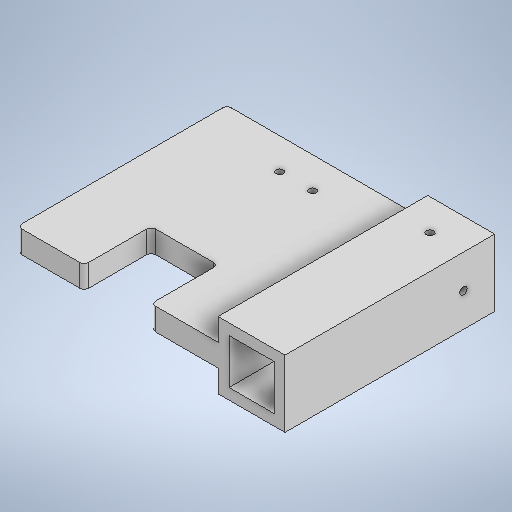
# Autodesk Inventor part: Sujetador_Camara
Saved by Autodesk Inventor 2025.3 (Build 293356030, 356C)
## iProperties
Created: 2026-03-05
Part Number: Sujetador_Camara
Material: Generic
Document SubType Name: Modeling
Designer: pablo
Density: 1 g/cm^3
Appearance: Default
Author: pablo
Autodesk Inventor part; units mm, degrees
ref_plane "YZ Plane" through (0, 0, 0) normal (1, 0, 0) x (0, 1, 0)
ref_plane "XZ Plane" through (0, 0, 0) normal (0, 1, 0) x (-1, 0, 0)
ref_plane "XY Plane" through (0, 0, 0) normal (0, 0, 1) x (1, 0, 0)
sketch "Sketch1" plane through (0, 0, 0) normal (0, 0, 1) x (1, 0, 0)
  line L0 (0, 0) -> (20.2, 0)
  line L1 (20.2, 0) -> (20.2, 20.2)
  line L2 (20.2, 20.2) -> (0, 20.2)
  line L3 (0, 20.2) -> (0, 0)
  line L4 (-4.9, -4.9) -> (25.1, -4.9)
  line L5 (25.1, -4.9) -> (25.1, 25.1)
  line L6 (25.1, 25.1) -> (-4.9, 25.1)
  line L7 (-4.9, 25.1) -> (-4.9, -4.9)
  dimension "d0" = 20.2
  dimension "d1" = 20.2
  dimension "d2" = 30
  dimension "d3" = 30
  dimension "d4" = 4.9
  dimension "d5" = 4.9
  constraints: 16 end point, 4 parallel, 2 horizontal, 2 perpendicular
  measures "d0" distance of L1.end L2.end
  measures "d1" distance of L0.end L1.end
  measures "d2" distance of L5.end L6.end
  measures "d3" distance of L4.end L5.end
  measures "d4" distance between parallel lines of L2 L6
  measures "d5" distance between parallel lines of L5 L1
extrude "Extrusion1" add sketch "Sketch1" along normal blind 94
sketch "Sketch2" plane through (-4.9, -4.9, 0) normal (-1, 0, 0) x (0, 0, 1)
  line L0 (0, 30) -> (0, 0) projected
  line L1 (0, 20) -> (94, 20)
  line L2 (94, 4.9) -> (94, 25.1) projected
  line L3 (0, 10) -> (94, 10)
  line L4 (0, 30) -> (94, 30) projected
  line L5 (0, 0) -> (94, 0) projected
  point P0 (0, 4.9)
  dimension "d8" = 10
  dimension "d9" = 10
  constraints: 4 end point, 4 point on line, 1 horizontal, 1 perpendicular
  measures "d8" distance between parallel lines of L4 L1
  measures "d9" distance between parallel lines of L5 L3
extrude "Extrusion2" add sketch "Sketch2" along normal blind 90
sketch "Sketch3" plane through (-4.9, 15.1, 94) normal (0, 1, 0) x (1, 0, 0)
  line L0 (0, 94) -> (-90, 94) projected
  line L1 (-90, 0) -> (-90, 94) projected
  point P0 (4.9, 94)
  point P1 (-52.366, 80)
  point P2 (-37.634, 80)
  point P3 (-45, 94)
  dimension "d12" = 14.732
  dimension "d13" = 7.366
  dimension "d14" = 14
  constraints: 1 horizontal alignment, 1 midpoint
  measures "d12" distance of point (-52.366, 80) point (-37.634, 80)
  measures "d13" horizontal distance of point (-45, 94) point (-37.634, 80)
  measures "d14" distance from line of L0 point (-52.366, 80)
hole "Hole1" at (-57.266, 15.1, 14) at (-42.534, 15.1, 14) direction (0, -1, 0) diameter 3.2 end through all
sketch "Sketch4" plane through (-4.9, 15.1, 94) normal (0, 1, 0) x (1, 0, 0)
  line L0 (-90, 0) -> (-90, 94) projected
  line L1 (0, 0) -> (-90, 0) projected
  line L2 (-60, 0) -> (-30, 0)
  line L3 (-30, 0) -> (-30, 30)
  line L4 (-30, 30) -> (-60, 30)
  line L5 (-60, 30) -> (-60, 0)
  point P0 (4.9, 94)
  point P1 (-45, 0)
  point P2 (-30, 0)
  dimension "d22" = 30
  dimension "d23" = 30
  dimension "d24" = 15
  constraints: 8 end point, 2 parallel, 1 horizontal, 1 midpoint, 1 perpendicular, 1 point on line
  measures "d22" distance of L3.end L4.end
  measures "d23" distance of L2.end L3.end
  measures "d24" distance of L2.start point (-45, 0)
extrude "Extrusion3" cut sketch "Sketch4" against normal through all
fillet "Fillet1" radius 2 2 edges at (-34.9, 10.1, 64) (-64.9, 10.1, 64)
fillet "Fillet2" radius 2 2 edges at (-94.9, 10.1, 94) (-94.9, 10.1, 0)
sketch "Sketch5" plane through (-4.9, 25.1, 0) normal (0, 1, 0) x (1, 0, 0)
  line L0 (30, 0) -> (0, 0) projected
  line L1 (30, 0) -> (30, -94) projected
  point P0 (4.9, 0)
  point P1 (15, -14)
  point P2 (15, 0)
  dimension "d29" = 14
  constraints: 1 midpoint, 1 vertical alignment
  measures "d29" distance from line of point (15, -14) L0
hole "Hole2" at (10.1, 25.1, 14) direction (0, -1, 0) diameter 3.302 end through all
sketch "Sketch7" plane through (25.1, -4.9, 0) normal (1, 0, 0) x (0, 0, -1)
  line L0 (0, 30) -> (-94, 30) projected
  line L1 (0, 0) -> (0, 30) projected
  line L2 (0, 0) -> (-94, 0) projected
  line L3 (-94, 0) -> (-94, 30) projected
  point P0 (0, 4.9)
  point P1 (-14, 15)
  point P2 (0, 15)
  point P3 (0, 15)
  dimension "d37" = 14
  constraints: 2 midpoint, 1 horizontal alignment
  measures "d37" distance of point (0, 15) point (-14, 15)
hole "Hole3" at (25.1, 10.1, 14) direction (-1, 0, 0) diameter 3.302 depth 4.9
body "Solid1"
